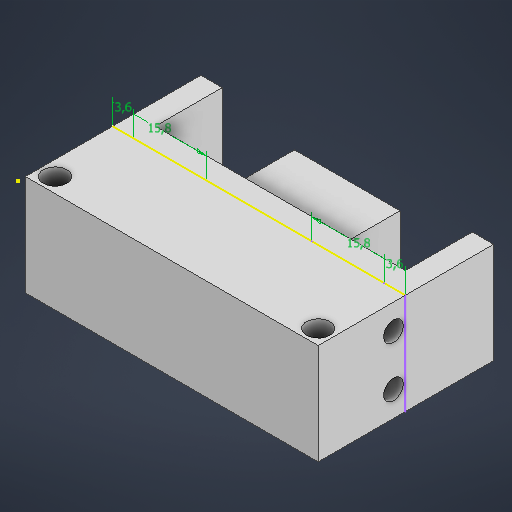
# Autodesk Inventor part: peça2
Saved by Autodesk Inventor 2026.2 (Build 302298010, 298A)
## iProperties
Created: 2026-04-17
Part Number: peça2
Material: Genérico
Document SubType Name: Modeling
Designer: a2453266
Density: 1 g/cm^3
Appearance: Padrão
Author: a2453266
## iProperties of the stored document peça2_3DPrint.ipt
Created: 2026-08-11
Part Number: peça2_3DPrint
Material: Genérico
Document SubType Name: Modeling
Designer: Admin
Density: 1 g/cm^3
Appearance: Padrão
Author: Admin
Autodesk Inventor part; units mm, degrees
ref_plane "YZ Plane" through (0, 0, 0) normal (1, 0, 0) x (0, 1, 0)
ref_plane "XZ Plane" through (0, 0, 0) normal (0, 1, 0) x (-1, 0, 0)
ref_plane "XY Plane" through (0, 0, 0) normal (0, 0, 1) x (1, 0, 0)
sketch "Esboço1" plane through (0, 0, 0) normal (0, 1, 0) x (-1, 0, 0)
  line L0 (0, 0) -> (-49.4, 0)
  line L1 (-49.4, 0) -> (-49.4, -15.9)
  line L2 (-49.4, -15.9) -> (0, -15.9)
  line L3 (0, -15.9) -> (0, 0)
  dimension "d0" = 49.4
  dimension "d1" = 15.9
  constraints: 8 end point, 2 parallel, 1 horizontal, 1 perpendicular
  measures "d0" distance of L2.end L1.end
  measures "d1" distance of L1.end L0.end
extrude "Extrusão1" add sketch "Esboço1" along normal blind 17
sketch "Esboço2" plane through (0, 17, 0) normal (0, 1, 0) x (1, 0, 0)
  line L0 (49.4, 15.9) -> (0, 15.9) projected
  line L1 (0, 15.9) -> (4.5, 15.9)
  line L2 (4.5, 15.9) -> (4.5, 11.4)
  line L3 (4.5, 11.4) -> (0, 11.4)
  line L4 (0, 11.4) -> (0, 15.9)
  line L5 (0, 0) -> (49.4, 0) projected
  line L6 (0, 0) -> (4.5, 0)
  line L7 (0, 4.5) -> (0, 0)
  line L8 (49.4, 0) -> (49.4, 15.9) projected
  line L9 (49.4, 15.9) -> (44.9, 15.9)
  line L10 (44.9, 15.9) -> (44.9, 11.4)
  line L11 (44.9, 11.4) -> (49.4, 11.4)
  line L12 (49.4, 11.4) -> (49.4, 15.9)
  line L13 (49.4, 0) -> (44.9, 0)
  line L14 (49.4, 4.5) -> (49.4, 0)
  line L15 (2.25, 15.9) -> (2.25, 11.4)
  line L16 (47.15, 15.9) -> (47.15, 11.4)
  circle A0 centre (2.25, 13.65) radius 1.6
  circle A1 centre (47.15, 13.65) radius 1.6
  line L17 (0, 0) -> (5, 0)
  line L18 (0, 5) -> (0, 0)
  line L19 (49.4, 0) -> (44.4, 0)
  line L20 (49.4, 5) -> (49.4, 0)
  line L21 (0, 0) -> (49.4, 0)
  line L22 (49.4, 0) -> (49.4, 1.2)
  line L23 (49.4, 1.2) -> (0, 1.2)
  line L24 (0, 1.2) -> (0, 0)
  line L25 (0, 1.2) -> (5, 1.2)
  line L26 (5, 1.2) -> (5, 6.2)
  line L27 (5, 6.2) -> (0, 6.2)
  line L28 (0, 6.2) -> (0, 1.2)
  line L29 (49.4, 1.2) -> (44.4, 1.2)
  line L30 (44.4, 1.2) -> (44.4, 6.2)
  line L31 (44.4, 6.2) -> (49.4, 6.2)
  line L32 (49.4, 6.2) -> (49.4, 1.2)
  line L33 (2.5, 6.2) -> (2.5, 1.2)
  line L34 (46.9, 6.2) -> (46.9, 1.2)
  circle A2 centre (2.5, 3.7) radius 2
  circle A3 centre (46.9, 3.7) radius 2
  dimension "d4" = 4.5
  dimension "d5" = 4.5
  dimension "d8" = 4.5
  dimension "d9" = 4.5
  dimension "d12" = 3.2
  dimension "d14" = 3.2
  dimension "d62" = 1.2
  dimension "d63" = 5
  dimension "d64" = 5
  dimension "d65" = 5
  dimension "d66" = 5
  dimension "d67" = 4
  dimension "d68" = 4
  constraints: 64 end point, 12 midpoint, 10 parallel, 9 horizontal, 5 perpendicular, 4 centre point, 1 point on line
  measures "d4" distance of L2.end L3.end
  measures "d5" distance of L1.end L2.end
  measures "d8" distance of L11.end L10.end
  measures "d9" distance of L10.end L9.end
  measures "d12" diameter of A0
  measures "d14" diameter of A1
  measures "d62" distance of L22.end L21.end
  measures "d63" distance of L27.end L26.end
  measures "d64" distance of L26.end L25.end
  measures "d65" distance of L30.end L31.end
  measures "d66" distance of L29.end L30.end
  measures "d67" diameter of A2
  measures "d68" diameter of A3
extrude "Extrusão2" cut sketch "Esboço2" against normal through all contours A3 L34 | L34 A3 | L8 L5 L7 L23 | A2 L33 | L33 A2
sketch "Esboço3" plane through (49.4, 0, -15.9) normal (0, 0, -1) x (-1, 0, 0)
  line L0 (49.4, 17) -> (0, 17) projected
  line L1 (49.4, 0) -> (33.6, 0)
  line L2 (33.6, 0) -> (33.6, 17)
  line L3 (33.6, 17) -> (49.4, 17)
  line L4 (49.4, 17) -> (49.4, 0)
  line L5 (0, 0) -> (15.8, 0)
  line L6 (15.8, 0) -> (15.8, 17)
  line L7 (15.8, 17) -> (0, 17)
  line L8 (0, 17) -> (0, 0)
  line L9 (33.6, 0) -> (15.8, 0)
  line L10 (15.8, 0) -> (15.8, 17)
  line L11 (15.8, 17) -> (33.6, 17)
  line L12 (33.6, 17) -> (33.6, 0)
  line L13 (49.4, 0) -> (45.8, 0)
  line L14 (45.8, 0) -> (45.8, 17)
  line L15 (45.8, 17) -> (49.4, 17)
  line L16 (49.4, 17) -> (49.4, 0)
  line L17 (0, 0) -> (3.6, 0)
  line L18 (3.6, 0) -> (3.6, 17)
  line L19 (3.6, 17) -> (0, 17)
  line L20 (0, 17) -> (0, 0)
  point P0 (15.8, 17)
  point P1 (0, 17)
  point P2 (3.6, 0)
  point P3 (3.6, 17)
  point P4 (45.8, 17)
  dimension "d18" = 15.8
  dimension "d19" = 15.8
  dimension "d24" = 3.6
  dimension "d25" = 3.6
  constraints: 40 end point, 10 parallel, 5 horizontal, 5 perpendicular, 5 point on line
  measures "d18" distance of L2.end L3.end
  measures "d19" distance of L7.end L6.end
  measures "d24" distance of L14.end L15.end
  measures "d25" distance of L19.end L18.end
extrude "Extrusão3" add sketch "Esboço3" along normal blind 14.9 contours L2 L9 L6 L0
extrude "Extrusão4" add sketch "Esboço3" along normal blind 3.6 contours L4 L1 L14 L0 | L14 L1 L2 L0 | L6 L5 L18 L0 | L18 L5 L8 L0
extrude "Extrusão5" add sketch "Esboço3" along normal blind 14.9 contours L4 L1 L14 L0 | L18 L5 L8 L0
sketch "Esboço4" plane through (49.4, 0, -30.8) normal (0, 0, -1) x (-1, 0, 0)
  point P0 (49.4, 0)
sketch "Esboço6" plane through (49.4, 0, -30.8) normal (0, 0, -1) x (-1, 0, 0)
  line L0 (33.6, 0) -> (33.6, 17) projected
  line L1 (15.8, 17) -> (15.8, 0) projected
  line L2 (33.6, 17) -> (15.8, 17)
  line L3 (15.8, 17) -> (15.8, 14)
  line L4 (15.8, 14) -> (33.6, 14)
  line L5 (33.6, 14) -> (33.6, 17)
  line L6 (33.6, 0) -> (15.8, 0)
  line L7 (15.8, 0) -> (15.8, 3)
  line L8 (15.8, 3) -> (33.6, 3)
  line L9 (33.6, 3) -> (33.6, 0)
  point P0 (49.4, 0)
  dimension "d39" = 3
  dimension "d40" = 3
  constraints: 16 end point, 4 parallel, 2 horizontal, 2 perpendicular, 2 point on line
  measures "d39" distance of L3.end L2.end
  measures "d40" distance of L6.end L7.end
extrude "Extrusão7" cut sketch "Esboço6" against normal blind 11.3 contours L6 L1 L8 L0 | L4 L1 L2 L0
sketch "Esboço7" plane through (49.4, 0, 0) normal (1, 0, 0) x (0, 0, -1)
  line L0 (0, 0) -> (0, 17) projected
  line L1 (1.2, 17) -> (30.8, 17) projected
  line L2 (0, 0) -> (15.9, 0)
  line L3 (15.9, 0) -> (15.9, 17)
  line L4 (15.9, 17) -> (0, 17)
  line L5 (0, 17) -> (0, 0)
  line L6 (15.9, 17) -> (15.9, 8.5)
  line L7 (15.9, 8.5) -> (15.9, 12.75)
  line L8 (15.9, 8.5) -> (15.9, 4.25)
  line L9 (15.9, 12.75) -> (13.9, 12.75)
  line L10 (15.9, 4.25) -> (13.9, 4.25)
  line L11 (13.9, 14.25) -> (15.4, 14.25)
  line L12 (15.4, 14.25) -> (15.4, 11.25)
  line L13 (15.4, 11.25) -> (13.9, 11.25)
  line L14 (13.9, 11.25) -> (13.9, 14.25)
  line L15 (13.9, 14.25) -> (12.4, 14.25)
  line L16 (12.4, 14.25) -> (12.4, 11.25)
  line L17 (12.4, 11.25) -> (13.9, 11.25)
  line L18 (13.9, 11.25) -> (13.9, 14.25)
  line L19 (13.9, 5.75) -> (15.4, 5.75)
  line L20 (15.4, 5.75) -> (15.4, 2.75)
  line L21 (15.4, 2.75) -> (13.9, 2.75)
  line L22 (13.9, 2.75) -> (13.9, 5.75)
  line L23 (13.9, 5.75) -> (12.4, 5.75)
  line L24 (12.4, 5.75) -> (12.4, 2.75)
  line L25 (12.4, 2.75) -> (13.9, 2.75)
  line L26 (13.9, 2.75) -> (13.9, 5.75)
  circle A0 centre (13.9, 12.75) radius 1.665
  circle A1 centre (13.9, 4.25) radius 1.665
  dimension "d43" = 8.5
  dimension "d44" = 4.25
  dimension "d45" = 4.25
  dimension "d46" = 2
  dimension "d47" = 2
  dimension "d58" = 3.33
  dimension "d59" = 3.33
  constraints: 50 end point, 10 parallel, 7 point on line, 6 horizontal, 6 perpendicular, 2 centre point, 2 coincident, 2 midpoint
  measures "d43" distance of L3.end L6.end
  measures "d44" distance of L6.end L7.end
  measures "d45" distance of L6.end L8.end
  measures "d46" distance of L7.end L9.end
  measures "d47" distance of L8.end L10.end
  measures "d58" diameter of A0
  measures "d59" diameter of A1
sketch "Esboço8" plane through (0, 17, 0) normal (0, 1, 0) x (1, 0, 0)
  point P0 (0, 0)
extrude "Extrusão8" cut sketch "Esboço7" against normal through all contours A1 L20 L10 | L10 L20 A1 | A0 L12 L9 | L9 L12 A0 | L20 A1 L21 L22 L10 | L10 L22 L19 A1 L20 | L22 L25 A1 L24 L23 | L19 L23 A1 | A1 L25 L21 | L12 A0 L13 L14 L9 | L9 L14 L11 A0 L12 | L14 L17 A0 L16 L15 | L11 L15 A0 | A0 L17 L13 | L24 A1 | L16 A0
sketch "Esboço9" plane through (49.4, 0, -30.8) normal (0, 0, -1) x (-1, 0, 0)
  point P0 (49.4, 0)
sketch "Esboço10" plane through (49.4, 0, -30.8) normal (0, 0, -1) x (-1, 0, 0)
  line L0 (15.8, 3) -> (33.6, 3) projected
  line L1 (24.7, 3) -> (24.7, 14)
  line L2 (33.6, 14) -> (15.8, 14) projected
  circle A0 centre (24.7, 8.5) radius 2
  point P0 (49.4, 0)
  dimension "d69" = 4
  constraints: 3 midpoint, 2 end point, 1 centre point
  measures "d69" diameter of A0
extrude "Extrusão9" cut sketch "Esboço10" against normal blind 10
